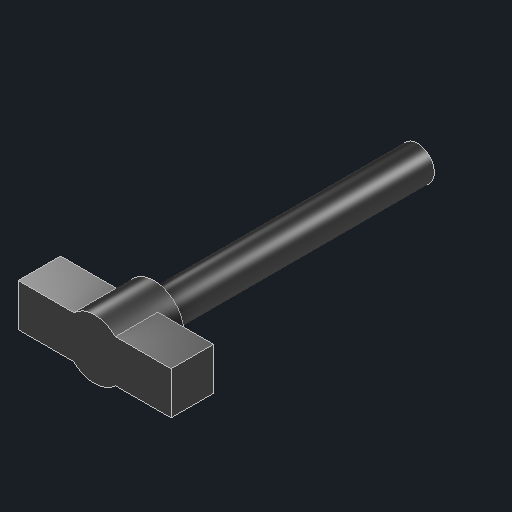
# Autodesk Inventor part: counterweight_lock_knob
Saved by Autodesk Inventor 2027.1 (Build 311270010, 270A)
## iProperties
Created: 2026-11-03
Part Number: counterweight_lock_knob
Material: Generic
Description: Counterweight lock thumb screw
Document SubType Name: Modeling
Designer: Claude (from photos)
Density: 1 g/cm^3
Appearance: Glossy - Black
Author: alexg
Autodesk Inventor part; units mm, degrees
ref_plane "YZ Plane" through (0, 0, 0) normal (1, 0, 0) x (0, 1, 0)
sketch "Thumb screw M8 sketch" plane through (0, 0, 0) normal (0, 0, 1) x (1, 0, 0)
  circle A0 centre (0, 0) radius 4
  constraints: 1 centre point
extrude "Thumb screw M8" add sketch "Thumb screw M8 sketch" along normal blind 74
ref_plane "Work Plane1" through (0, 0, 62) normal (0, 0, 1) x (1, 0, 0)
sketch "Hub sketch" plane through (0, 0, 62) normal (0, 0, 1) x (1, 0, 0)
  circle A0 centre (0, 0) radius 7
  constraints: 1 centre point
extrude "Hub" add sketch "Hub sketch" along normal blind 14
ref_plane "Work Plane2" through (0, 0, 66) normal (0, 0, 1) x (1, 0, 0)
sketch "Wing sketch" plane through (0, 0, 66) normal (0, 0, 1) x (1, 0, 0)
  line L0 (-18, -5) -> (18, -5)
  line L1 (18, -5) -> (18, 5)
  line L2 (18, 5) -> (-18, 5)
  line L3 (-18, 5) -> (-18, -5)
  constraints: 8 end point, 2 parallel, 1 horizontal, 1 perpendicular
extrude "Wing" add sketch "Wing sketch" along normal blind 10
body "Solid1"
